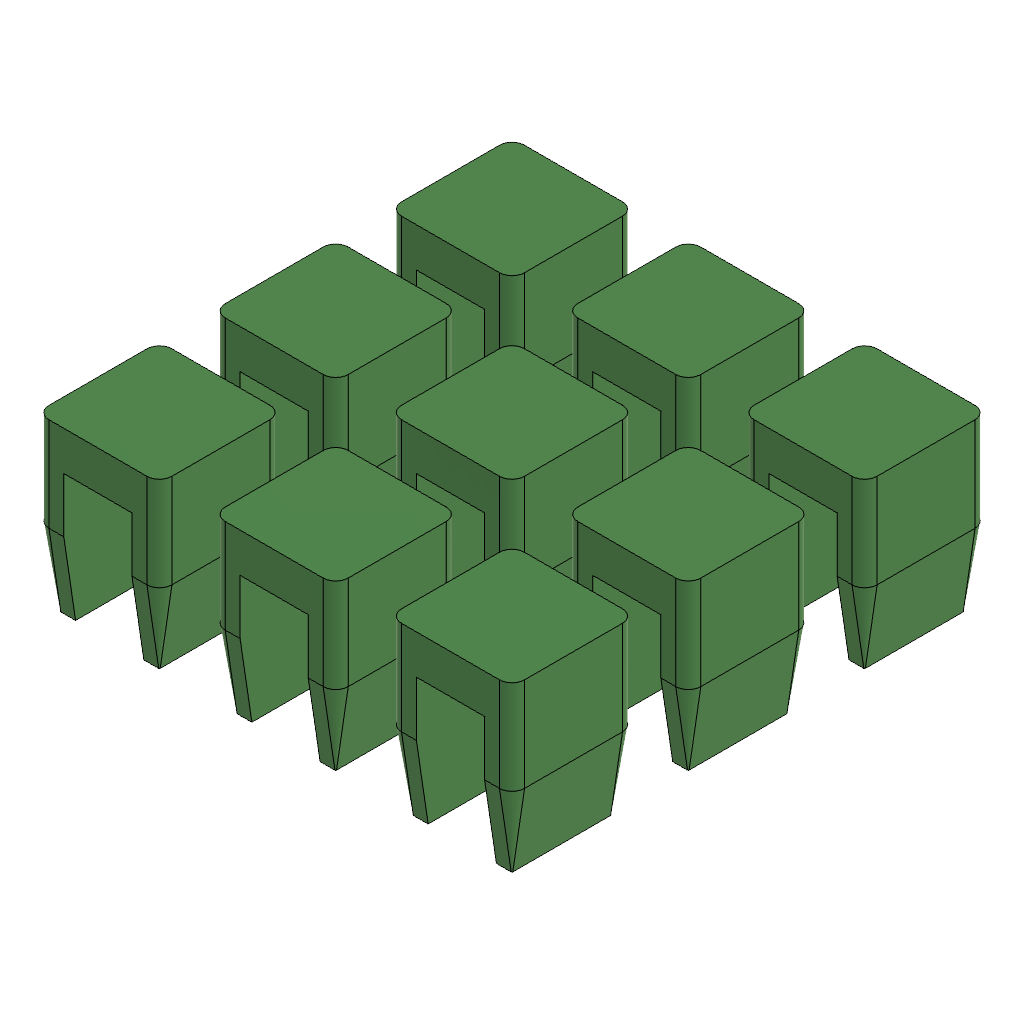
inserts-picker-tool (Autodesk Fusion 360 archive; units mm, degrees)
design "insert"
Autodesk Fusion 360 part; units mm, degrees
sketch "Hole Profile" plane through (0, 0, 0) normal (0, 0, 1) x (1, 0, 0)
  line L0 (-1.25, 1.75) -> (1.25, 1.75)
  line L1 (1.75, 1.25) -> (1.75, -1.25)
  line L2 (1.25, -1.75) -> (-1.25, -1.75)
  line L3 (-1.75, -1.25) -> (-1.75, 1.25)
  arc A0 (-1.25, 1.75) -> (-1.75, 1.25) centre (-1.25, 1.25) ccw
  arc A1 (1.75, 1.25) -> (1.25, 1.75) centre (1.25, 1.25) ccw
  arc A2 (1.25, -1.75) -> (1.75, -1.25) centre (1.25, -1.25) ccw
  arc A3 (-1.75, -1.25) -> (-1.25, -1.75) centre (-1.25, -1.25) ccw
  line L4 (0, 0) -> (1.75, 0) construction
  line L5 (0, 0) -> (0, 1.75) construction
  dimension "d1" = 0.5
  dimension "d2" = 3.5
  dimension "d3" = 3.5
  constraint horizontal L0
  constraint vertical L1
  constraint horizontal L2
  constraint vertical L3
  constraint tangent L0 A0
  constraint tangent L3 A0
  constraint tangent L0 A1
  constraint tangent L1 A1
  constraint equal A0 A1
  constraint tangent L1 A2
  constraint tangent L2 A2
  constraint equal A0 A2
  constraint tangent L2 A3
  constraint tangent L3 A3
  constraint equal A0 A3
  constraint coincident L4.start L5.start
  constraint midpoint L1 L4.end
  constraint midpoint L0 L5.end
  constraint horizontal L4
  constraint vertical L5
  measures "d1" radius of A0
  measures "d2" distance of L1 L3
  measures "d3" distance of L0 L2
sketch "Dot Profile" plane through (0, 0, 0) normal (0, 0, 1) x (1, 0, 0)
  line L0 (-1.25, 1.57) -> (1.25, 1.57)
  line L1 (1.57, 1.25) -> (1.57, -1.25)
  line L2 (1.25, -1.57) -> (-1.25, -1.57)
  line L3 (-1.57, -1.25) -> (-1.57, 1.25)
  arc A0 (-1.25, 1.57) -> (-1.57, 1.25) centre (-1.25, 1.25) ccw
  arc A1 (1.57, 1.25) -> (1.25, 1.57) centre (1.25, 1.25) ccw
  arc A2 (-1.57, -1.25) -> (-1.25, -1.57) centre (-1.25, -1.25) ccw
  arc A3 (1.25, -1.57) -> (1.57, -1.25) centre (1.25, -1.25) ccw
  line L4 (1.75, 1.25) -> (1.75, -1.25) construction
  arc A4 (-1.25, 1.75) -> (-1.75, 1.25) centre (-1.25, 1.25) ccw construction
  arc A5 (1.75, 1.25) -> (1.25, 1.75) centre (1.25, 1.25) ccw construction
  arc A6 (1.25, -1.75) -> (1.75, -1.25) centre (1.25, -1.25) ccw construction
  arc A7 (-1.75, -1.25) -> (-1.25, -1.75) centre (-1.25, -1.25) ccw construction
  line L5 (-1.25, 1.75) -> (1.25, 1.75) construction
  line L6 (-1.75, -1.25) -> (-1.75, 1.25) construction
  line L7 (1.25, -1.75) -> (-1.25, -1.75) construction
  dimension "d9" = 0.18
  dimension "d18" = 3.14
  dimension "d29" = 3.5
  constraint horizontal L0
  constraint vertical L1
  constraint horizontal L2
  constraint vertical L3
  constraint tangent L0 A0
  constraint tangent L3 A0
  constraint tangent L0 A1
  constraint tangent L1 A1
  constraint tangent L2 A2
  constraint tangent L3 A2
  constraint tangent L1 A3
  constraint tangent L2 A3
  constraint concentric A0 A4
  constraint concentric A1 A5
  constraint concentric A3 A6
  constraint concentric A2 A7
  measures "d9" distance of L1 L4
  measures "d18" distance of L1 L3
  measures "d29" distance of L4 L6
extrude "Extrude1" add sketch "Dot Profile" against normal blind 4.4 makes body 1
chamfer "Chamfer1" distance 0.3 distance2 2 8 edges at (0, -1.57, -4.4) (-1.4763, -1.4763, -4.4) (-1.57, 0, -4.4) (-1.4763, 1.4763, -4.4) (0, 1.57, -4.4) (1.4763, 1.4763, -4.4) (1.57, 0, -4.4) (1.4763, -1.4763, -4.4) measured on face at (0.4167, -0.5233, -4.4) measured on face at (0.4167, -0.5233, -4.4) measured on face at (0.4167, -0.5233, -4.4) measured on face at (0.4167, -0.5233, -4.4) measured on face at (0.4167, -0.5233, -4.4) measured on face at (0.4167, -0.5233, -4.4) measured on face at (0.4167, -0.5233, -4.4) measured on face at (0.4167, -0.5233, -4.4) tangent chain off on bodies 1
sketch "Sketch3" plane through (0, 0, 0) normal (0, 0, -1) x (1, 0, 0)
  arc A0 (-1.25, 1.27) -> (-1.27, 1.25) centre (-1.25, 1.25) ccw
  arc A1 (-1.27, -1.25) -> (-1.25, -1.27) centre (-1.25, -1.25) ccw
  arc A2 (1.25, -1.27) -> (1.27, -1.25) centre (1.25, -1.25) ccw
  line L0 (0.87, 1.57) -> (0.87, -1.57)
  line L1 (-0.87, -1.57) -> (-0.87, 1.57)
  arc A3 (-1.25, 1.57) -> (-1.57, 1.25) centre (-1.25, 1.25) ccw
  line L2 (-1.25, 1.57) -> (1.25, 1.57)
  arc A4 (1.57, 1.25) -> (1.25, 1.57) centre (1.25, 1.25) ccw
  line L3 (1.57, 1.25) -> (1.57, -1.25)
  arc A5 (1.25, -1.57) -> (1.57, -1.25) centre (1.25, -1.25) ccw
  line L4 (1.25, -1.57) -> (-1.25, -1.57)
  arc A6 (-1.57, -1.25) -> (-1.25, -1.57) centre (-1.25, -1.25) ccw
  line L5 (-1.57, -1.25) -> (-1.57, 1.25)
  line L6 (-1.27, -1.25) -> (-1.27, 1.25) construction
  line L7 (1.27, 1.25) -> (1.27, -1.25) construction
  dimension "d27" = 0.4
  dimension "d28" = 0.4
  constraint vertical L0
  constraint vertical L1
  constraint coincident L4 L1.start
  constraint coincident L4 L0.end
  constraint coincident L2 L1.end
  constraint coincident L2 L0.start
  measures "d27" distance of L1 L6
  measures "d28" distance of L0 L7
extrude "Extrude3" cut sketch "Sketch3" along normal through all from surface at 1 contours L0 L1 L2 L4 bodies 1
pattern_linear "Grid-Pattern (7x22)" count 3 spacing 4.5 along (1, 0, 0) count 3 spacing 4.5 along (0, 1, 0) of bodies 1 makes body 2 at (5.37, -0.4233, -3.0667) makes body 3 at (9.87, -0.4233, -3.0667) makes body 4 at (0.87, 4.0767, -3.0667) makes body 5 at (5.37, 4.0767, -3.0667) makes body 6 at (9.87, 4.0767, -3.0667) makes body 7 at (0.87, 9.4233, -3.0667) makes body 8 at (5.37, 9.4233, -3.0667) makes body 9 at (9.87, 9.4233, -3.0667)
named bodies: "insert", "insert (1)", "insert (2)", "insert (3)", "insert (4)", "insert (5)", "insert (6)", "insert (7)", "insert (8)"
